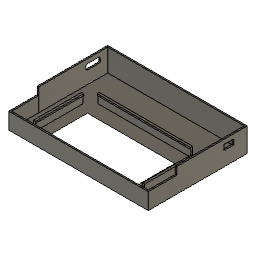
zh-tram-departure-board (Autodesk Fusion 360 design; units mm, degrees)
Autodesk Fusion 360 part; units mm, degrees
note: some values were not read from the file. Set by a fixed rule: which face or edge a step refers to.
sketch "Sketch2" plane through (0, 0, 0) normal (0, 0, 1) x (1, 0, 0)
  line L0 (0, 0) -> (93, 0)
  line L1 (93, 0) -> (93, 19)
  line L2 (93, 19) -> (0, 19)
  line L3 (0, 19) -> (0, 0)
  line L4 (0, 19) -> (93, 19)
  line L5 (93, 19) -> (93, 66)
  line L6 (93, 66) -> (0, 66)
  line L7 (0, 66) -> (0, 19)
  dimension "d1" = 93
  dimension "d2" = 19
  dimension "d3" = 66
  constraint horizontal L0
  constraint vertical L1
  constraint horizontal L2
  constraint vertical L3
  constraint coincident L0.start L3.end
  constraint horizontal L4
  constraint vertical L5
  constraint horizontal L6
  constraint vertical L7
  constraint collinear L1 L5
  measures "d1" distance of L1 L3
  measures "d2" distance of L0 L2
  measures "d3" distance of L0 L6
extrude "Extrude1" add sketch "Sketch2" along normal blind 11 contours L0 L1 L2 L3 L4
extrude "Extrude2" add sketch "Sketch2" along normal blind 15 contours L2 L4 L5 L6 L7
extrude "Extrude3" cut 1 faces at (31, 6.3333, 11) along direction (0, 0, -1) blind 1
shell "Shell1" thickness 1 removed faces 3 at (62, 19, 11.6667) at (31, 34.6667, 15) at (31, 6.3333, 10)
sketch "Sketch3" plane through (0, 0, 1) normal (0, 0, 1) x (-1, 0, 0)
  line L0 (-1, -1) -> (-92, -1)
  line L1 (-92, -1) -> (-92, -65)
  line L2 (-92, -65) -> (-1, -65)
  line L3 (-1, -65) -> (-1, -19)
  line L4 (-17.5, -5) -> (-75.5, -5)
  line L5 (-75.5, -5) -> (-75.5, -35)
  line L6 (-75.5, -35) -> (-17.5, -35)
  line L7 (-17.5, -35) -> (-17.5, -5)
  line L8 (-93, 0) -> (0, 0)
  line L9 (-1, -19) -> (-1, -1)
  dimension "d13" = 30
  dimension "d14" = 58
  dimension "d15" = 74.5
  dimension "d53" = 5
  constraint horizontal L4
  constraint vertical L5
  constraint horizontal L6
  constraint vertical L7
  measures "d13" distance of L4 L6
  measures "d14" distance of L5 L7
  measures "d15" distance of L1 L7
  measures "d53" distance of L4.end L8
extrude "Extrude4" cut sketch "Sketch3" against normal blind 7 contours L4 L5 L6 L7
chamfer "Chamfer1" distance 1 angle 45 4 edges at (46.5, 5, 0) (75.5, 20, 0) (46.5, 35, 0) (17.5, 20, 0)
sketch "Sketch4" plane through (0, 0, 1) normal (0, 0, 1) x (-1, 0, 0)
  line L0 (-75.5, -5) -> (-17.5, -5)
  line L1 (-17.5, -5) -> (-17.5, -35)
  line L2 (-17.5, -35) -> (-75.5, -35)
  line L3 (-75.5, -35) -> (-75.5, -5)
  line L4 (-1, -1) -> (-92, -1)
  line L5 (-92, -1) -> (-92, -65)
  line L6 (-92, -65) -> (-1, -65)
  line L7 (-1, -65) -> (-1, -19)
  line L8 (-83.5, -2.5) -> (-9.5, -2.5)
  line L9 (-9.5, -2.5) -> (-9.5, -47.5)
  line L10 (-9.5, -47.5) -> (-83.5, -47.5)
  line L11 (-83.5, -47.5) -> (-83.5, -2.5)
  line L12 (-1, -19) -> (-1, -1)
  dimension "d20" = 74
  dimension "d21" = 45
  constraint horizontal L8
  constraint vertical L9
  constraint horizontal L10
  constraint vertical L11
  measures "d20" distance of L8.start L8.end
  measures "d21" distance of L8.start L10.end
sketch "Sketch6" plane through (0, 0, 6) normal (0, 0, 1) x (-1, 0, 0)
  line L0 (-17.5, -47.5) -> (-9.5, -47.5)
  line L1 (-9.5, -47.5) -> (-9.5, -2.5)
  line L2 (-9.5, -2.5) -> (-83.5, -2.5)
  line L3 (-83.5, -2.5) -> (-83.5, -47.5)
  line L4 (-82.5, -46.5) -> (-82.5, -3.5)
  line L5 (-82.5, -3.5) -> (-10.5, -3.5)
  line L6 (-10.5, -3.5) -> (-10.5, -46.5)
  line L7 (-74.5, -46.5) -> (-82.5, -46.5)
  line L8 (-9.5, -47.5) -> (-14.5, -47.5)
  line L9 (-14.5, -47.5) -> (-14.5, -42.5)
  line L10 (-14.5, -42.5) -> (-9.5, -42.5)
  line L11 (-9.5, -42.5) -> (-9.5, -47.5)
  line L12 (-83.5, -47.5) -> (-83.5, -42.5)
  line L13 (-78.5, -47.5) -> (-83.5, -47.5)
  line L14 (-78.5, -42.5) -> (-78.5, -47.5)
  line L15 (-83.5, -42.5) -> (-78.5, -42.5)
  line L16 (-14.5, -7.5) -> (-14.5, -2.5)
  line L17 (-9.5, -7.5) -> (-14.5, -7.5)
  line L18 (-9.5, -2.5) -> (-9.5, -7.5)
  line L19 (-14.5, -2.5) -> (-9.5, -2.5)
  line L20 (-83.5, -7.5) -> (-83.5, -2.5)
  line L21 (-78.5, -7.5) -> (-83.5, -7.5)
  line L22 (-78.5, -2.5) -> (-78.5, -7.5)
  line L23 (-83.5, -2.5) -> (-78.5, -2.5)
  line L24 (-10.5, -46.5) -> (-16.5, -46.5)
  line L25 (-16.5, -46.5) -> (-16.5, -23.5)
  line L26 (-16.5, -23.5) -> (-74.5, -23.5)
  line L27 (-74.5, -23.5) -> (-74.5, -46.5)
  line L28 (-73.5, -47.5) -> (-73.5, -24.5)
  line L29 (-73.5, -24.5) -> (-17.5, -24.5)
  line L30 (-17.5, -24.5) -> (-17.5, -47.5)
  line L31 (-83.5, -47.5) -> (-73.5, -47.5)
  dimension "d29" = 5
  dimension "d30" = 5
  dimension "d33" = -69
  dimension "d34" = 40
  constraint horizontal L8
  constraint vertical L9
  constraint horizontal L10
  constraint vertical L11
  constraint coincident L0.end L1.start
  measures "d29" distance of L0.end L8.end
  measures "d30" distance of L0.end L10.end
sketch "Sketch7" plane through (0, 0, 0) normal (1, 0, 0) x (0, 1, 0)
  line L0 (60, 9.5) -> (50.5, 9.5)
  line L1 (50.5, 9.5) -> (50.5, 13)
  line L2 (50.5, 13) -> (60, 13)
  line L3 (60, 13) -> (60, 9.5)
  line L4 (66, 0) -> (66, 15)
  line L5 (66, 0) -> (19, 0)
  line L6 (66, 15) -> (19, 15)
  dimension "d37" = 9.5
  dimension "d38" = 3.5
  dimension "d41" = 15.5
  dimension "d52" = 2
  constraint horizontal L0
  constraint vertical L1
  constraint horizontal L2
  constraint vertical L3
  measures "d37" distance of L0.start L0.end
  measures "d38" distance of L0.start L2.end
  measures "d41" distance of L0.end L4
  measures "d52" distance of L2.end L6
extrude "Extrude7" cut sketch "Sketch7" along normal blind 2
fillet "Fillet1" radius 1 4 edges at (0.5, 60, 9.5) (0.5, 60, 13) (0.5, 50.5, 13) (0.5, 50.5, 9.5)
sketch "Sketch8" plane through (93, 0, 0) normal (1, 0, 0) x (0, 1, 0)
  line L0 (19, 15) -> (19, 10)
  line L1 (19, 10) -> (0, 10)
  line L2 (0, 10) -> (0, 0)
  line L3 (0, 0) -> (66, 0)
  line L4 (66, 0) -> (66, 15)
  line L5 (66, 15) -> (19, 15)
  line L6 (57, 13) -> (50.5, 13)
  line L7 (50.5, 13) -> (50.5, 9.5)
  line L8 (50.5, 9.5) -> (57, 9.5)
  line L9 (57, 9.5) -> (57, 13)
  dimension "d46" = 6.5
  dimension "d47" = 3.5
  dimension "d48" = 9
  dimension "d49" = 2
  constraint horizontal L6
  constraint vertical L7
  constraint horizontal L8
  constraint vertical L9
  measures "d46" distance of L6.start L6.end
  measures "d47" distance of L6.start L8.end
  measures "d48" distance of L4 L6.start
  measures "d49" distance of L5 L6.start
extrude "Extrude8" cut sketch "Sketch8" against normal blind 2 contours L6 L7 L8 L9
sketch "Sketch9" plane through (0, 0, 1) normal (0, 0, 1) x (-1, 0, 0)
  line L0 (-75.5, -5) -> (-17.5, -5)
  line L1 (-17.5, -5) -> (-17.5, -35)
  line L2 (-17.5, -35) -> (-75.5, -35)
  line L3 (-75.5, -35) -> (-75.5, -5)
  line L4 (-1, -1) -> (-92, -1)
  line L5 (-92, -1) -> (-92, -65)
  line L6 (-92, -65) -> (-1, -65)
  line L7 (-1, -65) -> (-1, -19)
  line L8 (-82.5, -1) -> (-10.5, -1)
  line L9 (-10.5, -1) -> (-10.5, -44)
  line L10 (-10.5, -44) -> (-82.5, -44)
  line L11 (-82.5, -44) -> (-82.5, -1)
  line L12 (-93, -19) -> (-93, 0)
  line L13 (-1, -19) -> (-1, -1)
  dimension "d54" = 72
  dimension "d55" = 43
  dimension "d56" = 10.5
  constraint horizontal L8
  constraint vertical L9
  constraint horizontal L10
  constraint vertical L11
  constraint coincident L4 L8.start
  measures "d54" distance of L8.start L8.end
  measures "d55" distance of L8.start L10.end
  measures "d56" distance of L8.start L12
extrude "Extrude9" add sketch "Sketch9" along normal blind 5 thin wall 1 outside contours L4 L8 L9 L10 L11
delete_face "DeleteFace1" 2 faces at (36.8333, 35, 2.6667) (55.8333, 5.3333, 6)
sketch "Sketch10" plane through (0, 0, 6) normal (0, 0, 1) x (-1, 0, 0)
  line L0 (-9.5, -1) -> (-10.5, -1)
  line L1 (-10.5, -1) -> (-10.5, -44)
  line L2 (-10.5, -44) -> (-82.5, -44)
  line L3 (-82.5, -44) -> (-82.5, -1)
  line L4 (-82.5, -1) -> (-83.5, -1)
  line L5 (-83.5, -1) -> (-83.5, -45)
  line L6 (-83.5, -45) -> (-9.5, -45)
  line L7 (-9.5, -45) -> (-9.5, -1)
  line L8 (-83.5, -45) -> (-77.5, -45)
  line L9 (-77.5, -45) -> (-77.5, -39)
  line L10 (-77.5, -39) -> (-83.5, -39)
  line L11 (-83.5, -39) -> (-83.5, -45)
  line L12 (-9.5, -45) -> (-15.5, -45)
  line L13 (-15.5, -45) -> (-15.5, -39)
  line L14 (-15.5, -39) -> (-9.5, -39)
  line L15 (-9.5, -39) -> (-9.5, -45)
  dimension "d60" = 6
  dimension "d61" = 6
  dimension "d62" = 6
  dimension "d63" = 6
  constraint horizontal L8
  constraint vertical L9
  constraint horizontal L10
  constraint vertical L11
  constraint coincident L5.end L6.start
  constraint horizontal L12
  constraint vertical L13
  constraint horizontal L14
  constraint vertical L15
  constraint coincident L6.end L7.start
  measures "d60" distance of L5.end L8.end
  measures "d61" distance of L5.end L10.end
  measures "d62" distance of L6.end L12.end
  measures "d63" distance of L6.end L14.end
extrude "Extrude10" cut sketch "Sketch10" against normal blind 5 contours L1 L2 L6 L7 L12 L13 L14 L15 | L1 L2 L13 L14 | L2 L3 L5 L6 L8 L9 L10 L11 | L2 L3 L9 L10
sketch "Sketch11" plane through (0, 0, 6) normal (0, 0, 1) x (-1, 0, 0)
  line L0 (-83.5, -39) -> (-82.5, -39)
  line L1 (-82.5, -39) -> (-82.5, -1)
  line L2 (-82.5, -1) -> (-83.5, -1)
  line L3 (-83.5, -1) -> (-83.5, -39)
  line L4 (-83.5, -1) -> (-79, -1)
  line L5 (-79, -1) -> (-79, -7)
  line L6 (-79, -7) -> (-83.5, -7)
  line L7 (-83.5, -7) -> (-83.5, -1)
  line L8 (-8, -1) -> (-13, -1)
  line L9 (-13, -1) -> (-13, -7)
  line L10 (-13, -7) -> (-8, -7)
  line L11 (-8, -7) -> (-8, -1)
  constraint horizontal L4
  constraint vertical L5
  constraint horizontal L6
  constraint vertical L7
  constraint coincident L2.end L3.start
  constraint horizontal L8
  constraint vertical L9
  constraint horizontal L10
  constraint vertical L11
extrude "Extrude11" cut sketch "Sketch11" against normal blind 5 contours L1 L2 L3 L4 L6 L7 | L1 L4 L5 L6 | L8 L9 L10 L11
extrude "Extrude12" add 1 faces at (31.3333, 65.6667, 15) along direction (0, 0, 1) blind 1
extrude "Extrude13" add 1 faces at (31.3333, 0.3333, 10) along direction (0, 0, 1) blind 1
sketch "Sketch12" plane through (0, 0, 6) normal (0, 0, 1) x (-1, 0, 0)
  line L0 (-82.5, -7) -> (-83.5, -7)
  line L1 (-83.5, -7) -> (-83.5, -39)
  line L2 (-83.5, -39) -> (-82.5, -39)
  line L3 (-82.5, -39) -> (-82.5, -7)
  line L4 (-83.5, -7) -> (-82, -7)
  line L5 (-82, -7) -> (-82, -39)
  line L6 (-82, -39) -> (-83.5, -39)
  line L7 (-83.5, -39) -> (-83.5, -7)
  constraint horizontal L4
  constraint vertical L5
  constraint horizontal L6
  constraint vertical L7
  constraint coincident L0.end L1.start
sketch "Sketch13" plane through (0, 0, 6) normal (0, 0, 1) x (-1, 0, 0)
  line L0 (-77.5, -44) -> (-77.5, -45)
  line L1 (-77.5, -45) -> (-15.5, -45)
  line L2 (-15.5, -45) -> (-15.5, -44)
  line L3 (-15.5, -44) -> (-77.5, -44)
  line L4 (-77.5, -45) -> (-15.5, -45)
  line L5 (-15.5, -45) -> (-15.5, -43.5)
  line L6 (-15.5, -43.5) -> (-77.5, -43.5)
  line L7 (-77.5, -43.5) -> (-77.5, -45)
  dimension "d72" = 1.5
  constraint horizontal L4
  constraint vertical L5
  constraint horizontal L6
  constraint vertical L7
  constraint coincident L0.end L1.start
  measures "d72" distance of L0.end L6.end
sketch "Sketch14" plane through (0, 0, 6) normal (0, 0, 1) x (-1, 0, 0)
  line L0 (-9.5, -7) -> (-10.5, -7)
  line L1 (-10.5, -7) -> (-10.5, -39)
  line L2 (-10.5, -39) -> (-9.5, -39)
  line L3 (-9.5, -39) -> (-9.5, -7)
  line L4 (-9.5, -7) -> (-11, -7)
  line L5 (-11, -7) -> (-11, -39)
  line L6 (-11, -39) -> (-9.5, -39)
  line L7 (-9.5, -39) -> (-9.5, -7)
  dimension "d73" = 1.5
  dimension "d74" = 32
  constraint horizontal L4
  constraint vertical L5
  constraint horizontal L6
  constraint vertical L7
  constraint coincident L0.start L3.end
  measures "d73" distance of L0.start L4.end
  measures "d74" distance of L0.start L2.end
extrude "Extrude14" add sketch "Sketch14" along normal blind 1
extrude "Extrude15" add sketch "Sketch13" along normal blind 1
extrude "Extrude16" add sketch "Sketch12" along normal blind 1
chamfer "Chamfer2" distance 0.5 angle 45 1 edges at (10.5, 23, 6)
chamfer "Chamfer3" distance 0.5 angle 45 1 edges at (46.5, 44, 6)
chamfer "Chamfer4" distance 0.5 angle 45 1 edges at (82.5, 23, 6)
